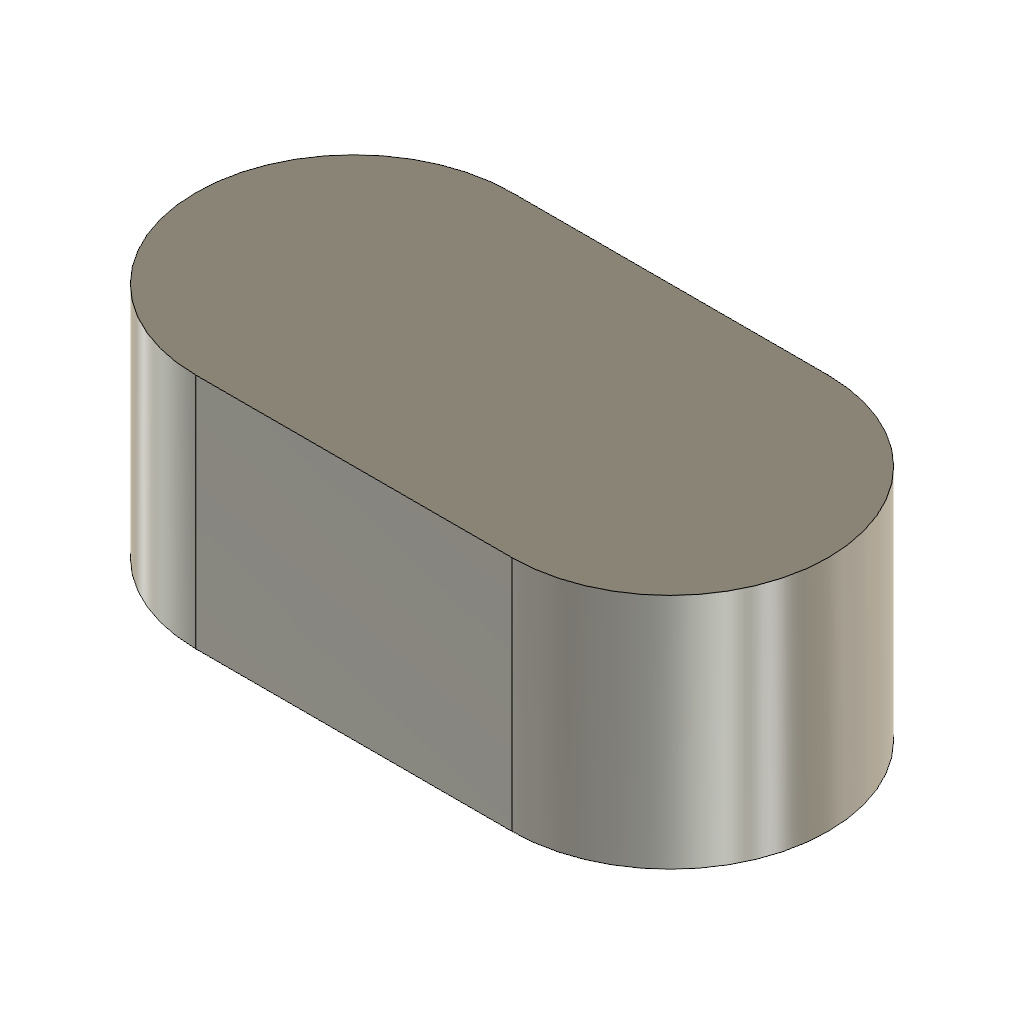
vendor_ProfileSlot (Autodesk Fusion 360 design; units mm, degrees)
Autodesk Fusion 360 part; units mm, degrees
sketch "Slot sketch" plane through (0, 0, 0) normal (0, 0, 1) x (1, 0, 0)
  line L0 (10, 0) -> (30, 0)
  arc A0 (30, 0) -> (30, 20) centre (30, 10) ccw
  line L1 (30, 20) -> (10, 20)
  arc A1 (10, 20) -> (10, 0) centre (10, 10) ccw
extrude "Slot extrude" add sketch "Slot sketch" along normal blind 15
equation "height = 20.0 mm"
